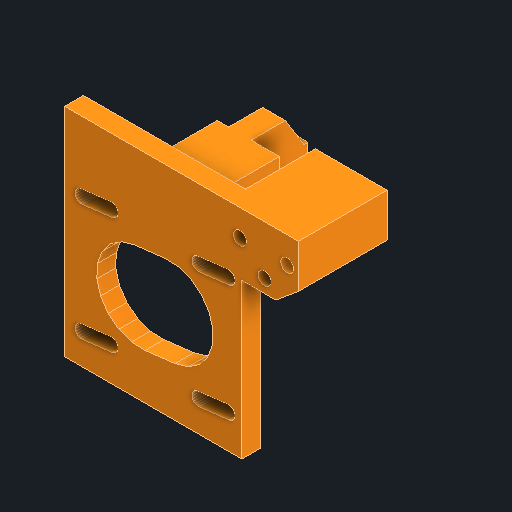
# Autodesk Inventor part: ra_motor_bracket
Saved by Autodesk Inventor 2027.1 (Build 311270010, 270A)
## iProperties
Created: 2026-11-04
Part Number: ra_motor_bracket
Material: Generic
Description: RA motor bracket: SELENO frame +Z wall (3x M3x30 into inserts) + tab on the flat bit +Z axial M5 (M5x20); motor slides +-4 mm along the belt; print PETG/ASA
Document SubType Name: Modeling
Designer: Claude (from photos)
Density: 1 g/cm^3
Appearance: Orange
Author: alexg
Autodesk Inventor part; units mm, degrees
ref_plane "Work Plane1" through (0, 0, 45) normal (0, 0, 1) x (1, 0, 0)
sketch "Foot block (sits on the frame +Z wall) sketch" plane through (0, 0, 45) normal (0, 0, 1) x (1, 0, 0)
  line L0 (31, -28) -> (37, -28)
  line L1 (37, -28) -> (37, -31)
  line L2 (37, -31) -> (44, -31)
  line L3 (44, -31) -> (50, -26)
  line L4 (50, -26) -> (50, -14.5)
  line L5 (50, -14.5) -> (31, -14.5)
  line L6 (31, -14.5) -> (31, -28)
  constraints: 14 end point
extrude "Foot block (sits on the frame +Z wall)" add sketch "Foot block (sits on the frame +Z wall) sketch" along normal blind 18.5
ref_plane "Work Plane2" through (0, 0, 63.5) normal (0, 0, 1) x (1, 0, 0)
sketch "Motor plate (slots +-4 along the belt) sketch" plane through (0, 0, 63.5) normal (0, 0, 1) x (1, 0, 0)
  line L0 (-12, -72) -> (35, -72)
  line L1 (35, -72) -> (35, -31)
  line L2 (35, -31) -> (44, -31)
  line L3 (44, -31) -> (50, -26)
  line L4 (50, -26) -> (50, -14.5)
  line L5 (50, -14.5) -> (-12, -14.5)
  line L6 (-12, -14.5) -> (-12, -72)
  line L7 (6.5982, -37.0577) -> (3.1367, -38.0395)
  line L8 (3.1367, -38.0395) -> (0.1481, -40.0428)
  line L9 (0.1481, -40.0428) -> (-2.0753, -42.8716)
  line L10 (-2.0753, -42.8716) -> (-3.3156, -46.2491)
  line L11 (-3.3156, -46.2491) -> (-3.4516, -49.8445)
  line L12 (-3.4516, -49.8445) -> (-2.4698, -53.306)
  line L13 (-2.4698, -53.306) -> (-0.4665, -56.2946)
  line L14 (-0.4665, -56.2946) -> (2.3623, -58.518)
  line L15 (2.3623, -58.518) -> (5.7398, -59.7583)
  line L16 (5.7398, -59.7583) -> (9.3352, -59.8943)
  line L17 (9.3352, -59.8943) -> (17.2784, -58.9423)
  line L18 (17.2784, -58.9423) -> (20.7398, -57.9605)
  line L19 (20.7398, -57.9605) -> (23.7285, -55.9572)
  line L20 (23.7285, -55.9572) -> (25.9518, -53.1284)
  line L21 (25.9518, -53.1284) -> (27.1922, -49.7509)
  line L22 (27.1922, -49.7509) -> (27.3281, -46.1555)
  line L23 (27.3281, -46.1555) -> (26.3464, -42.694)
  line L24 (26.3464, -42.694) -> (24.343, -39.7054)
  line L25 (24.343, -39.7054) -> (21.5142, -37.482)
  line L26 (21.5142, -37.482) -> (18.1368, -36.2417)
  line L27 (18.1368, -36.2417) -> (14.5413, -36.1057)
  line L28 (14.5413, -36.1057) -> (6.5982, -37.0577)
  line L29 (-7.7356, -62.2881) -> (-8.2473, -62.4332)
  line L30 (-8.2473, -62.4332) -> (-8.6891, -62.7294)
  line L31 (-8.6891, -62.7294) -> (-9.0178, -63.1475)
  line L32 (-9.0178, -63.1475) -> (-9.2011, -63.6468)
  line L33 (-9.2011, -63.6468) -> (-9.2212, -64.1783)
  line L34 (-9.2212, -64.1783) -> (-9.0761, -64.69)
  line L35 (-9.0761, -64.69) -> (-8.7799, -65.1318)
  line L36 (-8.7799, -65.1318) -> (-8.3618, -65.4605)
  line L37 (-8.3618, -65.4605) -> (-7.8625, -65.6438)
  line L38 (-7.8625, -65.6438) -> (-7.331, -65.6639)
  line L39 (-7.331, -65.6639) -> (0.6122, -64.7119)
  line L40 (0.6122, -64.7119) -> (1.1238, -64.5668)
  line L41 (1.1238, -64.5668) -> (1.5657, -64.2706)
  line L42 (1.5657, -64.2706) -> (1.8943, -63.8525)
  line L43 (1.8943, -63.8525) -> (2.0777, -63.3532)
  line L44 (2.0777, -63.3532) -> (2.0978, -62.8217)
  line L45 (2.0978, -62.8217) -> (1.9526, -62.31)
  line L46 (1.9526, -62.31) -> (1.6565, -61.8682)
  line L47 (1.6565, -61.8682) -> (1.2383, -61.5395)
  line L48 (1.2383, -61.5395) -> (0.739, -61.3562)
  line L49 (0.739, -61.3562) -> (0.2076, -61.3361)
  line L50 (0.2076, -61.3361) -> (-7.7356, -62.2881)
  line L51 (-7.7356, -31.2881) -> (-8.2473, -31.4332)
  line L52 (-8.2473, -31.4332) -> (-8.6891, -31.7294)
  line L53 (-8.6891, -31.7294) -> (-9.0178, -32.1475)
  line L54 (-9.0178, -32.1475) -> (-9.2011, -32.6468)
  line L55 (-9.2011, -32.6468) -> (-9.2212, -33.1783)
  line L56 (-9.2212, -33.1783) -> (-9.0761, -33.69)
  line L57 (-9.0761, -33.69) -> (-8.7799, -34.1318)
  line L58 (-8.7799, -34.1318) -> (-8.3618, -34.4605)
  line L59 (-8.3618, -34.4605) -> (-7.8625, -34.6438)
  line L60 (-7.8625, -34.6438) -> (-7.331, -34.6639)
  line L61 (-7.331, -34.6639) -> (0.6122, -33.7119)
  line L62 (0.6122, -33.7119) -> (1.1238, -33.5668)
  line L63 (1.1238, -33.5668) -> (1.5657, -33.2706)
  line L64 (1.5657, -33.2706) -> (1.8943, -32.8525)
  line L65 (1.8943, -32.8525) -> (2.0777, -32.3532)
  line L66 (2.0777, -32.3532) -> (2.0978, -31.8217)
  line L67 (2.0978, -31.8217) -> (1.9526, -31.31)
  line L68 (1.9526, -31.31) -> (1.6565, -30.8682)
  line L69 (1.6565, -30.8682) -> (1.2383, -30.5395)
  line L70 (1.2383, -30.5395) -> (0.739, -30.3562)
  line L71 (0.739, -30.3562) -> (0.2076, -30.3361)
  line L72 (0.2076, -30.3361) -> (-7.7356, -31.2881)
  line L73 (23.2644, -62.2881) -> (22.7527, -62.4332)
  line L74 (22.7527, -62.4332) -> (22.3109, -62.7294)
  line L75 (22.3109, -62.7294) -> (21.9822, -63.1475)
  line L76 (21.9822, -63.1475) -> (21.7989, -63.6468)
  line L77 (21.7989, -63.6468) -> (21.7788, -64.1783)
  line L78 (21.7788, -64.1783) -> (21.9239, -64.69)
  line L79 (21.9239, -64.69) -> (22.2201, -65.1318)
  line L80 (22.2201, -65.1318) -> (22.6382, -65.4605)
  line L81 (22.6382, -65.4605) -> (23.1375, -65.6438)
  line L82 (23.1375, -65.6438) -> (23.669, -65.6639)
  line L83 (23.669, -65.6639) -> (31.6122, -64.7119)
  line L84 (31.6122, -64.7119) -> (32.1238, -64.5668)
  line L85 (32.1238, -64.5668) -> (32.5657, -64.2706)
  line L86 (32.5657, -64.2706) -> (32.8943, -63.8525)
  line L87 (32.8943, -63.8525) -> (33.0777, -63.3532)
  line L88 (33.0777, -63.3532) -> (33.0978, -62.8217)
  line L89 (33.0978, -62.8217) -> (32.9526, -62.31)
  line L90 (32.9526, -62.31) -> (32.6565, -61.8682)
  line L91 (32.6565, -61.8682) -> (32.2383, -61.5395)
  line L92 (32.2383, -61.5395) -> (31.739, -61.3562)
  line L93 (31.739, -61.3562) -> (31.2076, -61.3361)
  line L94 (31.2076, -61.3361) -> (23.2644, -62.2881)
  line L95 (23.2644, -31.2881) -> (22.7527, -31.4332)
  line L96 (22.7527, -31.4332) -> (22.3109, -31.7294)
  line L97 (22.3109, -31.7294) -> (21.9822, -32.1475)
  line L98 (21.9822, -32.1475) -> (21.7989, -32.6468)
  line L99 (21.7989, -32.6468) -> (21.7788, -33.1783)
  line L100 (21.7788, -33.1783) -> (21.9239, -33.69)
  line L101 (21.9239, -33.69) -> (22.2201, -34.1318)
  line L102 (22.2201, -34.1318) -> (22.6382, -34.4605)
  line L103 (22.6382, -34.4605) -> (23.1375, -34.6438)
  line L104 (23.1375, -34.6438) -> (23.669, -34.6639)
  line L105 (23.669, -34.6639) -> (31.6122, -33.7119)
  line L106 (31.6122, -33.7119) -> (32.1238, -33.5668)
  line L107 (32.1238, -33.5668) -> (32.5657, -33.2706)
  line L108 (32.5657, -33.2706) -> (32.8943, -32.8525)
  line L109 (32.8943, -32.8525) -> (33.0777, -32.3532)
  line L110 (33.0777, -32.3532) -> (33.0978, -31.8217)
  line L111 (33.0978, -31.8217) -> (32.9526, -31.31)
  line L112 (32.9526, -31.31) -> (32.6565, -30.8682)
  line L113 (32.6565, -30.8682) -> (32.2383, -30.5395)
  line L114 (32.2383, -30.5395) -> (31.739, -30.3562)
  line L115 (31.739, -30.3562) -> (31.2076, -30.3361)
  line L116 (31.2076, -30.3361) -> (23.2644, -31.2881)
  constraints: 234 end point
extrude "Motor plate (slots +-4 along the belt)" add sketch "Motor plate (slots +-4 along the belt) sketch" along normal blind 5
ref_plane "Work Plane3" through (0, 0, 45) normal (0, 0, 1) x (1, 0, 0)
sketch "M3 clearance holes sketch" plane through (0, 0, 45) normal (0, 0, 1) x (1, 0, 0)
  circle A0 centre (34.5, -21.5) radius 1.7
  circle A1 centre (47, -21.5) radius 1.7
  circle A2 centre (41, -27.5) radius 1.7
  constraints: 3 centre point
extrude "M3 clearance holes" cut sketch "M3 clearance holes sketch" along normal blind 23.5
ref_plane "Work Plane4" through (7, 0, 0) normal (1, 0, 0) x (0, 1, 0)
sketch "Tab on flat bit polar face sketch" plane through (7, 0, 0) normal (1, 0, 0) x (0, 1, 0)
  line L0 (-42, 29) -> (-42, 44.5)
  line L1 (-42, 44.5) -> (-22, 44.5)
  line L2 (-22, 44.5) -> (-22, 35)
  line L3 (-22, 35) -> (-30, 30)
  line L4 (-30, 30) -> (-30, 29)
  line L5 (-30, 29) -> (-42, 29)
  constraints: 12 end point
extrude "Tab on flat bit polar face" add sketch "Tab on flat bit polar face sketch" along normal blind 6
ref_plane "Work Plane5" through (0, -37.5, 0) normal (0, 1, 0) x (-1, 0, 0)
sketch "Web from plate to tab sketch" plane through (0, -37.5, 0) normal (0, 1, 0) x (-1, 0, 0)
  line L0 (-4, 44) -> (-20.5, 44)
  line L1 (-20.5, 44) -> (-20.5, 64)
  line L2 (-20.5, 64) -> (-4, 64)
  line L3 (-4, 64) -> (-4, 44)
  constraints: 8 end point, 2 parallel, 1 horizontal, 1 perpendicular
extrude "Web from plate to tab" add sketch "Web from plate to tab sketch" along normal blind 15.5
ref_plane "Work Plane6" through (7, 0, 0) normal (1, 0, 0) x (0, 1, 0)
sketch "M5 hole (6 mm, +-0.5 float) sketch" plane through (7, 0, 0) normal (1, 0, 0) x (0, 1, 0)
  circle A0 centre (-37, 34.5) radius 3
  constraints: 1 centre point
extrude "M5 hole (6 mm, +-0.5 float)" cut sketch "M5 hole (6 mm, +-0.5 float) sketch" along normal blind 6
body "Solid1"
